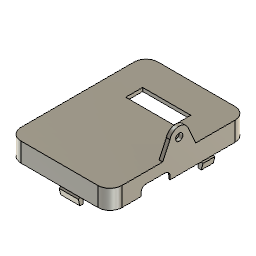
Wireless Motion Sensor (Autodesk Fusion 360 design; units mm, degrees)
Autodesk Fusion 360 part; units mm, degrees
sketch "perf board sketch" plane through (0, 0, 0) normal (0, 0, 1) x (1, 0, 0) in component "Perf"
  line L0 (16, 25) -> (-16, 25)
  line L1 (-16, 25) -> (-16, -25)
  line L2 (-16, -25) -> (16, -25)
  line L3 (16, -25) -> (16, 25)
  line L4 (16, 25) -> (-16, -25) construction
  line L5 (-16, 25) -> (16, -25) construction
  dimension "d12" = 32
  dimension "d13" = 50
  constraint horizontal L0
  constraint perpendicular L0 L1
  constraint parallel L0 L2
  constraint parallel L1 L3
  constraint coincident L4 origin
  constraint coincident L5 origin
  measures "d12" distance of L1.end L2.end
  measures "d13" distance of L0.end L1.end
extrude "Extrusion of the perf board body." add sketch "perf board sketch" along normal blind 1.2 makes body 1 in component "Perf"
sketch "dSensor board sketch" plane through (0, 0, 0) normal (0, 0, 1) x (1, 0, 0) in component "DSensor"
  line L0 (7, 3.1) -> (-13, 3.1)
  line L1 (-15.5, 5.6) -> (-15.5, 18.4)
  line L2 (-13, 20.9) -> (7, 20.9)
  line L3 (9.5, 18.4) -> (9.5, 5.6)
  line L4 (9.5, 3.1) -> (-15.5, 20.9) construction
  line L5 (-15.5, 3.1) -> (9.5, 20.9) construction
  line L6 (0, 2.5) -> (0, 20) construction
  line L7 (20, 0) -> (2.5, 0) construction
  line L8 (-3, 12) -> (-3, 17) construction
  line L9 (-3, 12) -> (-7, 12) construction
  circle A0 centre (-13.46, 18.86) radius 1.2
  circle A1 centre (7.46, 18.86) radius 1.2
  circle A2 centre (7.46, 5.14) radius 1.2
  circle A3 centre (-13.46, 5.14) radius 1.2
  arc A4 (-13, 20.9) -> (-15.5, 18.4) centre (-13, 18.4) ccw
  arc A5 (9.5, 18.4) -> (7, 20.9) centre (7, 18.4) ccw
  arc A6 (7, 3.1) -> (9.5, 5.6) centre (7, 5.6) ccw
  arc A7 (-15.5, 5.6) -> (-13, 3.1) centre (-13, 5.6) ccw
  point P0 (-3, 12)
  dimension "d16" = 25
  dimension "d17" = 17.8
  dimension "d18" = 3
  dimension "d19" = 12
  dimension "d20" = 2.4
  dimension "d21" = 2.04
  dimension "d22" = 2.04
  dimension "d23" = 2.5
  constraint horizontal L0
  constraint perpendicular L0 L1
  constraint parallel L0 L2
  constraint parallel L1 L3
  constraint coincident L4 P0
  constraint coincident L5 P0
  constraint coincident P0 L8.start
  constraint vertical L8
  constraint perpendicular L8 L9
  constraint symmetric L8 A0 A1
  constraint symmetric L9 A0 A3
  constraint symmetric L9 A1 A2
  constraint coincident L4.end L1
  constraint coincident L4.end L2
  constraint tangent L1 A4
  constraint tangent L2 A4
  constraint coincident L5.end L2
  constraint coincident L5.end L3
  constraint tangent L2 A5
  constraint tangent L3 A5
  constraint equal A4 A5
  constraint coincident L4.start L3
  constraint coincident L4.start L0
  constraint tangent L3 A6
  constraint tangent L0 A6
  constraint equal A4 A6
  constraint coincident L5.start L0
  constraint coincident L5.start L1
  constraint tangent L0 A7
  constraint tangent L1 A7
  constraint equal A4 A7
  measures "d16" distance of L4.end L5.end
  measures "d17" distance of L5.start L4.end
  measures "d18" distance of P0 L6
  measures "d19" distance of P0 L7
  measures "d20" diameter of A0
  measures "d21" distance of L1 A0.centre
  measures "d22" distance of L2 A0.centre
  measures "d23" radius of A4
extrude "Extrusion of the dSensor board body." add sketch "dSensor board sketch" along normal blind 1.6 separate body makes body 2 in component "DSensor"
sketch "wemos board sketch" plane through (0, 0, 0) normal (0, 0, 1) x (1, 0, 0) in component "Wemos"
  line L0 (17.5, 2) -> (-14.5, 2)
  line L1 (-17.5, -1) -> (-17.5, -20)
  line L2 (-14.5, -23) -> (17.5, -23)
  line L3 (17.5, -23) -> (17.5, 2)
  line L4 (17.5, 2) -> (-17.5, -23) construction
  line L5 (-17.5, 2) -> (17.5, -23) construction
  line L6 (-17.5, -1) -> (-14.5, 2)
  line L7 (-17.5, -20) -> (-14.5, -23)
  line L8 (17.5, -18) -> (16, -18)
  line L9 (16, -18) -> (16, -9.5)
  line L10 (16, -9.5) -> (17.5, -9.5)
  line L11 (17.5, -9.5) -> (17.5, -18)
  line L12 (0, 1.75) -> (0, 22.5)
  line L13 (20, 0) -> (2.5, 0)
  point P0 (0, -10.5)
  dimension "d26" = 35
  dimension "d27" = 25
  dimension "d28" = 3
  dimension "d29" = 3
  dimension "d30" = 3
  dimension "d31" = 3
  dimension "d32" = 5
  dimension "d33" = 8.5
  dimension "d34" = 10.5
  constraint horizontal L0
  constraint perpendicular L0 L1
  constraint parallel L0 L2
  constraint parallel L1 L3
  constraint coincident L4 P0
  constraint coincident L5 P0
  constraint coincident L5.start L1
  constraint coincident L5.start L0
  constraint coincident L4.end L1
  constraint coincident L4.end L2
  constraint horizontal L8
  constraint vertical L9
  constraint horizontal L10
  constraint vertical L11
  constraint coincident L3 L8.start
  constraint coincident P0 L12
  measures "d26" distance of L4.end L2.end
  measures "d27" distance of L5.start L4.end
  measures "d28" distance of L5.start L1.start
  measures "d29" distance of L5.start L0.end
  measures "d30" distance of L4.end L1.end
  measures "d31" distance of L4.end L2.start
  measures "d32" distance of L2 L8
  measures "d33" distance of L8 L10
  measures "d34" distance of P0 L13
extrude "Extrusion of the wemos board body." add sketch "wemos board sketch" along normal blind 1.2 separate body contours L0 L1 L2 L3 L6 L7 L8 L9 L10 makes body 3 in component "Wemos"
sketch "housing outline sketch" plane through (0, 0, 0) normal (0, 0, 1) x (1, 0, 0) in component "Housing"
  line L0 (-16, -28.5) -> (16, -28.5)
  line L1 (21, -23.5) -> (21, 23.5)
  line L2 (16, 28.5) -> (-16, 28.5)
  line L3 (-21, 23.5) -> (-21, -23.5)
  line L4 (-21, -28.5) -> (21, 28.5) construction
  line L5 (21, -28.5) -> (-21, 28.5) construction
  circle A0 centre (0, 34) radius 1.5
  circle A1 centre (0, 34) radius 2.5
  circle A2 centre (0, 34) radius 4
  line L6 (0, 1.75) -> (0, 22.5)
  line L7 (-3.8706, 35.0092) -> (-6.9059, 28.5)
  line L8 (-3.8706, 35.0092) -> (3.3115, 35.0092) construction
  line L9 (3.8706, 35.0092) -> (6.2397, 28.5)
  line L10 (20, 0) -> (2.5, 0)
  circle A3 centre (0, -34) radius 1.5
  circle A4 centre (0, -34) radius 2.5
  circle A5 centre (0, -34) radius 4
  line L11 (-3.8706, -35.0092) -> (-6.9059, -28.5)
  line L12 (3.8706, -35.0092) -> (6.2397, -28.5)
  arc A6 (-16, 28.5) -> (-21, 23.5) centre (-16, 23.5) ccw
  arc A7 (21, 23.5) -> (16, 28.5) centre (16, 23.5) ccw
  arc A8 (-21, -23.5) -> (-16, -28.5) centre (-16, -23.5) ccw
  arc A9 (16, -28.5) -> (21, -23.5) centre (16, -23.5) ccw
  line L13 (-19.5, 23.5) -> (-19.5, -23.5)
  arc A10 (-19.5, -23.5) -> (-16, -27) centre (-16, -23.5) ccw
  line L14 (-16, -27) -> (16, -27)
  arc A11 (16, -27) -> (19.5, -23.5) centre (16, -23.5) ccw
  line L15 (19.5, -23.5) -> (19.5, 23.5)
  arc A12 (19.5, 23.5) -> (16, 27) centre (16, 23.5) ccw
  line L16 (16, 27) -> (-16, 27)
  arc A13 (-16, 27) -> (-19.5, 23.5) centre (-16, 23.5) ccw
  line L17 (-20.1, 23.5) -> (-20.1, -23.5)
  arc A14 (-20.1, -23.5) -> (-16, -27.6) centre (-16, -23.5) ccw
  line L18 (-16, -27.6) -> (16, -27.6)
  arc A15 (16, -27.6) -> (20.1, -23.5) centre (16, -23.5) ccw
  line L19 (20.1, -23.5) -> (20.1, 23.5)
  arc A16 (20.1, 23.5) -> (16, 27.6) centre (16, 23.5) ccw
  line L20 (16, 27.6) -> (-16, 27.6)
  arc A17 (-16, 27.6) -> (-20.1, 23.5) centre (-16, 23.5) ccw
  line L21 (-20.4, 23.5) -> (-20.4, -23.5)
  arc A18 (-20.4, -23.5) -> (-16, -27.9) centre (-16, -23.5) ccw
  line L22 (-16, -27.9) -> (16, -27.9)
  arc A19 (16, -27.9) -> (20.4, -23.5) centre (16, -23.5) ccw
  line L23 (20.4, -23.5) -> (20.4, 23.5)
  arc A20 (20.4, 23.5) -> (16, 27.9) centre (16, 23.5) ccw
  line L24 (16, 27.9) -> (-16, 27.9)
  arc A21 (-16, 27.9) -> (-20.4, 23.5) centre (-16, 23.5) ccw
  line L25 (10, 9.1) -> (-10, 9.1)
  line L26 (-10, 9.1) -> (-10, 16.1)
  line L27 (-10, 16.1) -> (10, 16.1)
  line L28 (10, 16.1) -> (10, 9.1)
  line L29 (10, 9.1) -> (-10, 16.1) construction
  line L30 (-10, 9.1) -> (10, 16.1) construction
  line L31 (5, -15) -> (-10, -15)
  line L32 (-10, -15) -> (-10, -5)
  line L33 (-10, -5) -> (5, -5)
  line L34 (5, -5) -> (5, -15)
  line L35 (5, -15) -> (-10, -5) construction
  line L36 (-10, -15) -> (5, -5) construction
  line L37 (16, 25) -> (-16, 25)
  line L38 (-16, -25) -> (16, -25)
  line L39 (-7, 25) -> (-7, 23) construction
  line L40 (-5, -25) -> (-5, -23) construction
  line L41 (-5, -23) -> (-19.5, -23)
  line L42 (-5, -23) -> (-5, -27)
  line L43 (-5, 27) -> (-5, 23)
  line L44 (-5, 23) -> (-19.5, 23)
  line L45 (-10.5, 23) -> (-10.5, 27)
  line L46 (-10.5, -23) -> (-10.5, -27)
  line L47 (-14.5, -27) -> (-14.5, -23)
  line L48 (-14.5, 23) -> (-14.5, 27)
  line L49 (-3.8706, 35.0092) -> (-3.8706, 28.5) construction
  line L50 (-3.8706, 28.5) -> (-6.9059, 28.5) construction
  line L51 (-16, -27) -> (-16, -23)
  line L52 (-16, 23) -> (-16, 27)
  point P0 (0, 12.6)
  point P1 (-2.5, -10)
  dimension "d43" = 42
  dimension "d44" = 57
  dimension "d47" = 3
  dimension "d48" = 1
  dimension "d49" = 1.5
  dimension "d50" = 5.5
  dimension "d53" = 115
  dimension "d54" = 135
  dimension "d55" = 5
  dimension "d58" = -0.9
  dimension "d59" = -0.6
  dimension "d60" = 20
  dimension "d61" = 7
  dimension "d62" = 15
  dimension "d63" = 15
  dimension "d64" = 10
  dimension "d65" = 17
  dimension "d66" = 17
  dimension "d67" = 2
  dimension "d68" = 2
  dimension "d69" = 14.5
  dimension "d70" = 4
  dimension "d115" = 9
  dimension "d116" = 9
  dimension "d117" = 5
  dimension "d118" = 5
  constraint horizontal L0
  constraint perpendicular L0 L1
  constraint parallel L0 L2
  constraint parallel L1 L3
  constraint coincident L4 origin
  constraint coincident L5 origin
  constraint coincident A0.centre L6
  constraint horizontal L8
  constraint coincident A2 L7.start
  constraint coincident L2 L7.end
  constraint coincident A2 L9.start
  constraint coincident L2 L9.end
  constraint symmetric A0 L10 A3
  constraint symmetric A1 L10 A4
  constraint symmetric A2 L10 A5
  constraint symmetric L7.start L10 L11.start
  constraint symmetric L7.end L10 L11.end
  constraint symmetric L9.start L10 L12.start
  constraint symmetric L9.end L10 L12.end
  constraint coincident L5.end L3
  constraint coincident L5.end L2
  constraint tangent L3 A6
  constraint tangent L2 A6
  constraint coincident L4.end L2
  constraint coincident L4.end L1
  constraint tangent L2 A7
  constraint tangent L1 A7
  constraint equal A6 A7
  constraint coincident L4.start L3
  constraint coincident L4.start L0
  constraint tangent L3 A8
  constraint tangent L0 A8
  constraint equal A6 A8
  constraint coincident L5.start L1
  constraint coincident L5.start L0
  constraint tangent L1 A9
  constraint tangent L0 A9
  constraint equal A6 A9
  constraint horizontal L25
  constraint perpendicular L25 L26
  constraint parallel L25 L27
  constraint parallel L26 L28
  constraint coincident L29 P0
  constraint coincident L30 P0
  constraint coincident L6 P0
  constraint horizontal L31
  constraint perpendicular L31 L32
  constraint parallel L31 L33
  constraint parallel L32 L34
  constraint coincident L35 P1
  constraint coincident L36 P1
  constraint coincident L37 L39.start
  constraint perpendicular L37 L39
  constraint coincident L38 L40.start
  constraint perpendicular L38 L40
  constraint coincident L13 L41.end
  constraint perpendicular L13 L41
  constraint coincident L14 L42.end
  constraint perpendicular L14 L42
  constraint coincident L16 L43.start
  constraint perpendicular L37 L43
  constraint coincident L13 L44.end
  constraint perpendicular L13 L44
  constraint coincident L44 L45.start
  constraint coincident L16 L45.end
  constraint perpendicular L16 L45
  constraint coincident L41 L46.start
  constraint coincident L14 L46.end
  constraint perpendicular L14 L46
  constraint coincident L14 L47.start
  constraint coincident L41 L47.end
  constraint perpendicular L41 L47
  constraint coincident L44 L48.start
  constraint coincident L16 L48.end
  constraint perpendicular L16 L48
  constraint coincident L2 L49.end
  constraint perpendicular L2 L49
  constraint coincident L41 L51.end
  constraint perpendicular L41 L51
  constraint coincident L44 L52.start
  measures "d43" distance of L4.end L5.end
  measures "d44" distance of L5.start L4.end
  measures "d47" diameter of A0
  measures "d50" distance of L2 A0.centre
  measures "d53" angle of L7 L8
  measures "d54" angle of L7 L9
  measures "d55" radius of A6
  measures "d60" distance of L26.end L27.end
  measures "d61" distance of L25.end L26.end
  measures "d62" distance of L20 P0
  measures "d63" distance of L32.end L33.end
  measures "d64" distance of L31.end L32.end
  measures "d65" distance of L13 P1
  measures "d66" distance of L14 P1
  measures "d67" distance of L39.start L39.end
  measures "d68" distance of L40.start L40.end
  measures "d69" distance of L43.end L44.end
  measures "d70" distance of L43.start L43.end
  measures "d115" distance of L13 L46
  measures "d116" distance of L13 L45
  measures "d117" distance of L13 L47
  measures "d118" distance of L13 L48
extrude "Extrusion of the housing's bottom base body." add sketch "housing outline sketch" along normal blind 1.5 from surface at -9.5 separate body contours L0 L1 L2 L3 A6 A7 A8 A9 | L0 A5 L11 L12 | A5 | L2 A2 L7 L9 | A2 | A1 | L6 L25 L26 L27 | L6 L25 L27 L28 | A4 | L13 A13 L44 L52 | L13 L14 A11 L15 A12 L16 L41 L42 L43 L44 | L16 L37 L48 L52 | L13 A10 L41 L51 | L37 L44 L48 L52 | L16 L37 L45 L48 | L38 L41 L47 L51 | L37 L44 L45 L48 | L16 L37 L43 L45 | L14 L38 L47 L51 | L38 L41 L46 L47 | L37 L43 L44 L45 | L14 L38 L46 L47 | L38 L41 L42 L46 | L14 L38 L42 L46 | L17 A14 L18 A15 L19 A16 L20 A17 | L21 A18 L22 A19 L23 A20 L24 A21 | L31 L32 L33 L34 makes body 4 in component "Housing"
extrude "Extrusion of the housing's bottom pcb stand off." add sketch "housing outline sketch" along normal blind 3 from surface at -8 contours L31 L32 L33 L34 bodies 4 in component "Housing"
extrude "Extrusion of the housing's bottom body outside walls." add sketch "housing outline sketch" against normal up to surface (8 mm away) contours L0 L1 L2 L3 A6 A7 A8 A9 | L17 A14 L18 A15 L19 A16 L20 A17 | L21 A18 L22 A19 L23 A20 L24 A21 bodies 4 in component "Housing"
extrude "Extrusion of the housing's bottom mounting holes support." add sketch "housing outline sketch" along normal blind 1.5 from surface at -8 contours L0 A5 L11 L12 | A5 | L2 A2 L7 L9 | A2 bodies 4 in component "Housing"
extrude "Extrusion of the housing's bottom body walls rim." add sketch "housing outline sketch" along normal blind 2.5 contours L17 A14 L18 A15 L19 A16 L20 A17 bodies 4 in component "Housing"
extrude "Extrusion of the housing's top body base." add sketch "housing outline sketch" along normal blind 1.5 from surface at 6.5 separate body contours L0 L1 L2 L3 A6 A7 A8 A9 | L13 A13 L44 L52 | L13 L14 A11 L15 A12 L16 L41 L42 L43 L44 | L16 L37 L48 L52 | L13 A10 L41 L51 | L37 L44 L48 L52 | L16 L37 L45 L48 | L38 L41 L47 L51 | L37 L44 L45 L48 | L16 L37 L43 L45 | L14 L38 L47 L51 | L38 L41 L46 L47 | L37 L43 L44 L45 | L14 L38 L46 L47 | L38 L41 L42 L46 | L14 L38 L42 L46 | L17 A14 L18 A15 L19 A16 L20 A17 | L21 A18 L22 A19 L23 A20 L24 A21 | L31 L32 L33 L34 makes body 5 in component "Housing"
extrude "Extrusion of the housing's top body outside walls." add sketch "housing outline sketch" along normal up to surface (6.5 mm away) contours L0 L1 L2 L3 A6 A7 A8 A9 | L17 A14 L18 A15 L19 A16 L20 A17 | L21 A18 L22 A19 L23 A20 L24 A21 bodies 5 in component "Housing"
extrude "Extrusion cutout of the housing's top body walls rim." cut sketch "housing outline sketch" along normal blind 2.8 contours L17 A14 L18 A15 L19 A16 L20 A17 | L21 A18 L22 A19 L23 A20 L24 A21 bodies 5 in component "Housing"
sketch "components outline sketch" plane through (0, 0, 1.6) normal (0, 0, 1) x (1, 0, 0) in component "DSensor"
  circle A0 centre (-13.46, 5.14) radius 1.2
  circle A1 centre (-13.46, 18.86) radius 1.2
  circle A2 centre (7.46, 18.86) radius 1.2
  circle A3 centre (7.46, 5.14) radius 1.2
  arc A4 (-13, 20.9) -> (-15.5, 18.4) centre (-13, 18.4) ccw
  line L0 (-15.5, 18.4) -> (-15.5, 5.6)
  arc A5 (-15.5, 5.6) -> (-13, 3.1) centre (-13, 5.6) ccw
  line L1 (-13, 3.1) -> (7, 3.1)
  arc A6 (7, 3.1) -> (9.5, 5.6) centre (7, 5.6) ccw
  line L2 (9.5, 5.6) -> (9.5, 18.4)
  arc A7 (9.5, 18.4) -> (7, 20.9) centre (7, 18.4) ccw
  line L3 (7, 20.9) -> (-13, 20.9)
  line L4 (-1.5, 9.5) -> (-4.5, 9.5)
  line L5 (-4.5, 9.5) -> (-4.5, 14.5)
  line L6 (-4.5, 14.5) -> (-1.5, 14.5)
  line L7 (-1.5, 14.5) -> (-1.5, 9.5)
  line L8 (-1.5, 9.5) -> (-4.5, 14.5) construction
  line L9 (-4.5, 9.5) -> (-1.5, 14.5) construction
  line L10 (-11, 8.75) -> (-15.5, 8.75)
  line L11 (-15.5, 8.75) -> (-15.5, 15.25)
  line L12 (-15.5, 15.25) -> (-11, 15.25)
  line L13 (-11, 15.25) -> (-11, 8.75)
  line L14 (-11, 8.75) -> (-15.5, 15.25) construction
  line L15 (-15.5, 8.75) -> (-11, 15.25) construction
  line L16 (9.5, 8.75) -> (5, 8.75)
  line L17 (5, 8.75) -> (5, 15.25)
  line L18 (5, 15.25) -> (9.5, 15.25)
  line L19 (9.5, 15.25) -> (9.5, 8.75)
  line L20 (9.5, 8.75) -> (5, 15.25) construction
  line L21 (5, 8.75) -> (9.5, 15.25) construction
  circle A8 centre (-13.46, 5.14) radius 1.2
  circle A9 centre (-13.46, 18.86) radius 1.2
  circle A10 centre (7.46, 18.86) radius 1.2
  circle A11 centre (7.46, 5.14) radius 1.2
  arc A12 (-13, 20.9) -> (-15.5, 18.4) centre (-13, 18.4) ccw
  line L22 (-15.5, 18.4) -> (-15.5, 5.6)
  arc A13 (-15.5, 5.6) -> (-13, 3.1) centre (-13, 5.6) ccw
  line L23 (-13, 3.1) -> (7, 3.1)
  arc A14 (7, 3.1) -> (9.5, 5.6) centre (7, 5.6) ccw
  line L24 (9.5, 5.6) -> (9.5, 18.4)
  arc A15 (9.5, 18.4) -> (7, 20.9) centre (7, 18.4) ccw
  line L25 (7, 20.9) -> (-13, 20.9)
  point P0 (-3, 12)
  point P1 (-13.25, 12)
  point P2 (7.25, 12)
  dimension "d85" = 3
  dimension "d86" = 5
  dimension "d87" = 12.5
  dimension "d88" = 8.9
  dimension "d89" = 4.5
  dimension "d90" = 6.5
  dimension "d91" = 8.9
  dimension "d92" = 6.5
  dimension "d93" = 4.5
  dimension "d94" = 8.9
  constraint horizontal L4
  constraint perpendicular L4 L5
  constraint parallel L4 L6
  constraint parallel L5 L7
  constraint coincident L8 P0
  constraint coincident L9 P0
  constraint horizontal L10
  constraint perpendicular L10 L11
  constraint parallel L10 L12
  constraint parallel L11 L13
  constraint coincident L14 P1
  constraint coincident L15 P1
  constraint collinear L0 L11
  constraint horizontal L16
  constraint perpendicular L16 L17
  constraint parallel L16 L18
  constraint parallel L17 L19
  constraint coincident L20 P2
  constraint coincident L21 P2
  constraint collinear L2 L19
  measures "d85" distance of L5.end L6.end
  measures "d86" distance of L4.end L5.end
  measures "d87" distance of L0 P0
  measures "d88" distance of L3 P0
  measures "d89" distance of L11.end L12.end
  measures "d90" distance of L10.end L11.end
  measures "d91" distance of L1 P1
  measures "d92" distance of L16 L18
  measures "d93" distance of L17 L19
  measures "d94" distance of L1 P2
extrude "Extrusion of the dSensor's sensor body." add sketch "components outline sketch" along normal blind 1.5 separate body contours L4 L5 L6 L7 makes body 6 in component "DSensor"
extrude "Extrusion of the dSensor's connectors bodies." add sketch "components outline sketch" along normal blind 3 separate body contours L0 L10 L11 L12 L13 L22 | L2 L16 L17 L18 L19 L24 makes body 7 at (-14, 13.0833, 1.6) makes body 8 at (6.5, 13.0833, 1.6) in component "DSensor"
sketch "components outline sketch (2)" plane through (0, 0, 1.2) normal (0, 0, 1) x (-1, 0, 0) in component "Wemos"
  line L0 (17.5, 1) -> (17.5, 20)
  line L1 (17.5, 20) -> (14.5, 23)
  line L2 (14.5, 23) -> (-17.5, 23)
  line L3 (-17.5, 23) -> (-17.5, 18)
  line L4 (-17.5, 18) -> (-16, 18)
  line L5 (-16, 18) -> (-16, 9.5)
  line L6 (-16, 9.5) -> (-17.5, 9.5)
  line L7 (-17.5, 9.5) -> (-17.5, -2)
  line L8 (-17.5, -2) -> (14.5, -2)
  line L9 (14.5, -2) -> (17.5, 1)
  line L10 (-4.5, 16.5) -> (10.5, 16.5)
  line L11 (10.5, 16.5) -> (10.5, 4.5)
  line L12 (10.5, 4.5) -> (-4.5, 4.5)
  line L13 (-4.5, 4.5) -> (-4.5, 16.5)
  line L14 (-4.5, 16.5) -> (10.5, 4.5) construction
  line L15 (10.5, 16.5) -> (-4.5, 4.5) construction
  point P0 (3, 10.5)
  dimension "d99" = 15
  dimension "d100" = 12
  dimension "d101" = 12.5
  dimension "d102" = 7
  constraint horizontal L10
  constraint perpendicular L10 L11
  constraint parallel L10 L12
  constraint parallel L11 L13
  constraint coincident L14 P0
  constraint coincident L15 P0
  measures "d99" distance of L11.end L12.end
  measures "d100" distance of L10.end L11.end
  measures "d101" distance of L2 P0
  measures "d102" distance of L0 L11
extrude "Extrusion of the wemos's wifi mod body." add sketch "components outline sketch (2)" along normal blind 3 separate body contours L10 L11 L12 L13 makes body 9 in component "Wemos"
sketch "headers outline sketch" plane through (0, 0, 0) normal (0, 0, -1) x (1, 0, 0) in component "Headers"
  line L0 (16, -25) -> (16, 25)
  line L1 (16, 25) -> (-16, 25)
  line L2 (-16, 25) -> (-16, -25)
  line L3 (-16, -25) -> (16, -25)
  line L4 (-12.7415, 20.1248) -> (12, 20.1248)
  line L5 (12, 20.1248) -> (12, 17.6248)
  line L6 (12, 17.6248) -> (-12.7415, 17.6248)
  line L7 (-12.7415, 17.6248) -> (-12.7415, 20.1248)
  line L8 (-12.7415, 3.2784) -> (12, 3.2784)
  line L9 (12, 3.2784) -> (12, 0.7784)
  line L10 (12, 0.7784) -> (-12.7415, 0.7784)
  line L11 (-12.7415, 0.7784) -> (-12.7415, 3.2784)
  line L12 (-11, -17) -> (5.4615, -17)
  line L13 (5.4615, -17) -> (5.4615, -19.5)
  line L14 (5.4615, -19.5) -> (-11, -19.5)
  line L15 (-11, -19.5) -> (-11, -17)
  dimension "d105" = 2.5
  dimension "d106" = 2.5
  dimension "d107" = 2.5
  constraint horizontal L4
  constraint vertical L5
  constraint horizontal L6
  constraint vertical L7
  constraint horizontal L8
  constraint vertical L9
  constraint horizontal L10
  constraint vertical L11
  constraint horizontal L12
  constraint vertical L13
  constraint horizontal L14
  constraint vertical L15
  measures "d105" distance of L4.start L6.end
  measures "d106" distance of L8.start L10.end
  measures "d107" distance of L12.start L14.end
extrude "Extrusion of the header's rows bodies." add sketch "headers outline sketch" along normal blind 5 separate body contours L4 L5 L6 L7 | L8 L9 L10 L11 | L12 L13 L14 L15 makes body 10 at (-4.4943, -20.1248, -1.6667) makes body 11 at (-4.4943, -3.2784, -1.6667) makes body 12 at (-5.5128, 17, -1.6667) in component "Headers"
extrude "Extrusion of the housing's bottom body pcb's top supports." add sketch "housing outline sketch" against normal blind 1.5 contours L13 A13 L44 L52 | L16 L37 L48 L52 | L13 A10 L41 L51 | L37 L44 L48 L52 | L16 L37 L45 L48 | L38 L41 L47 L51 | L37 L44 L45 L48 | L14 L38 L47 L51 | L38 L41 L46 L47 | L14 L38 L46 L47 bodies 4 in component "Housing"
extrude "Extrusion of the housing's bottom pcb's bottom supports." add sketch "housing outline sketch" against normal blind 1.5 from surface at -3 contours L13 A13 L44 L52 | L16 L37 L48 L52 | L13 A10 L41 L51 | L37 L44 L48 L52 | L16 L37 L45 L48 | L38 L41 L47 L51 | L37 L44 L45 L48 | L16 L37 L43 L45 | L14 L38 L47 L51 | L38 L41 L46 L47 | L37 L43 L44 L45 | L14 L38 L46 L47 | L38 L41 L42 L46 | L14 L38 L42 L46 bodies 4 in component "Housing"
extrude "Extrusion of the housing's bottom pcb's supports stop." add sketch "housing outline sketch" against normal up to surface (3 mm away) contours L13 A13 L44 L52 | L13 A10 L41 L51 bodies 4 in component "Housing"
sketch "housing's snap insert outline sketch x-z plane" plane through (0, -27, 0) normal (0, 1, 0) x (-1, 0, 0) in component "Housing"
  line L0 (16, -1.5) -> (10.5, -1.5)
  line L1 (10.5, -1.5) -> (10.5, 0)
  line L2 (10.5, 0) -> (16, 0)
  line L3 (16, 0) -> (16, 2.5)
  line L4 (16, 2.5) -> (-16, 2.5)
  line L5 (-16, 2.5) -> (-16, -8)
  line L6 (-16, -8) -> (16, -8)
  line L7 (16, -8) -> (16, -4.5)
  line L8 (16, -4.5) -> (5, -4.5)
  line L9 (5, -4.5) -> (5, -3)
  line L10 (5, -3) -> (16, -3)
  line L11 (1.15, -1.1) -> (-7.15, -1.1)
  line L12 (-7.15, -1.1) -> (-7.15, -4.9)
  line L13 (-7.15, -4.9) -> (1.15, -4.9)
  line L14 (1.15, -4.9) -> (1.15, -1.1)
  line L15 (1.15, -1.1) -> (-7.15, -4.9) construction
  line L16 (-7.15, -1.1) -> (1.15, -4.9) construction
  line L17 (1, 7.4) -> (-7, 7.4)
  line L18 (-7, 7.4) -> (-7, -4.6)
  line L19 (-7, -4.6) -> (1, -4.6)
  line L20 (1, -4.6) -> (1, 7.4)
  line L21 (1, 7.4) -> (-7, -4.6) construction
  line L22 (-7, 7.4) -> (1, -4.6) construction
  line L23 (16, -3) -> (16, -1.5)
  line L24 (-7.15, -1.1) -> (-7.15, -3.1) construction
  line L25 (-7.15, -3.1) -> (1.15, -3.1)
  point P0 (-3, -3)
  point P1 (-3, 1.4)
  dimension "d127" = 8.3
  dimension "d128" = 3.8
  dimension "d129" = 5
  dimension "d130" = 13
  dimension "d157" = 8
  dimension "d158" = 12
  dimension "d159" = 13
  dimension "d160" = 0.3
  dimension "d205" = 2
  constraint horizontal L11
  constraint perpendicular L11 L12
  constraint parallel L11 L13
  constraint parallel L12 L14
  constraint coincident L15 P0
  constraint coincident L16 P0
  constraint horizontal L17
  constraint perpendicular L17 L18
  constraint parallel L17 L19
  constraint parallel L18 L20
  constraint coincident L21 P1
  constraint coincident L22 P1
  constraint perpendicular L11 L24
  constraint coincident L14 L25.end
  constraint perpendicular L14 L25
  measures "d127" distance of L12.end L13.end
  measures "d128" distance of L11.end L12.end
  measures "d129" distance of L6 P0
  measures "d130" distance of L5 P0
  measures "d157" distance of L18.end L19.end
  measures "d158" distance of L17.end L18.end
  measures "d159" distance of L5 P1
  measures "d160" distance of L13 L19
  measures "d205" distance of L11.end L24.end
sketch "housing's snap insert outline sketch z-y plane" plane through (-19.5, 0, 0) normal (1, 0, 0) x (0, 1, 0) in component "Housing"
  line L0 (23, -4.5) -> (23, 0)
  line L1 (23, 0) -> (23.5, 0)
  line L2 (23.5, 0) -> (23.5, 2.5)
  line L3 (23.5, 2.5) -> (-23.5, 2.5)
  line L4 (-23.5, 2.5) -> (-23.5, 0)
  line L5 (-23.5, 0) -> (-23, 0)
  line L6 (-23, 0) -> (-23, -4.5)
  line L7 (-23, -4.5) -> (-23.5, -4.5)
  line L8 (-23.5, -4.5) -> (-23.5, -8)
  line L9 (-23.5, -8) -> (23.5, -8)
  line L10 (23.5, -8) -> (23.5, -4.5)
  line L11 (23.5, -4.5) -> (23, -4.5)
  line L12 (-10.85, -4.75) -> (-16.15, -4.75)
  line L13 (-16.15, -4.75) -> (-16.15, -1.25)
  line L14 (-16.15, -1.25) -> (-10.85, -1.25)
  line L15 (-10.85, -1.25) -> (-10.85, -4.75)
  line L16 (-10.85, -4.75) -> (-16.15, -1.25) construction
  line L17 (-16.15, -4.75) -> (-10.85, -1.25) construction
  line L18 (0, 2.5) -> (0, 20)
  line L19 (16.15, -1.25) -> (10.85, -1.25)
  line L20 (16.15, -4.75) -> (16.15, -1.25)
  line L21 (10.85, -4.75) -> (16.15, -4.75)
  line L22 (10.85, -1.25) -> (10.85, -4.75)
  line L23 (-11, 7.55) -> (-16, 7.55)
  line L24 (-16, 7.55) -> (-16, -4.45)
  line L25 (-16, -4.45) -> (-11, -4.45)
  line L26 (-11, -4.45) -> (-11, 7.55)
  line L27 (-11, 7.55) -> (-16, -4.45) construction
  line L28 (-16, 7.55) -> (-11, -4.45) construction
  point P0 (-13.5, -3)
  point P1 (-13.5, 1.55)
  dimension "d133" = 5.3
  dimension "d134" = 3.5
  dimension "d135" = 10
  dimension "d136" = 5
  dimension "d161" = 5
  dimension "d162" = 12
  dimension "d163" = 10
  dimension "d164" = 0.3
  constraint horizontal L12
  constraint perpendicular L12 L13
  constraint parallel L12 L14
  constraint parallel L13 L15
  constraint coincident L16 P0
  constraint coincident L17 P0
  constraint symmetric L12.start L18 L21.start
  constraint symmetric L12.end L18 L20.start
  constraint symmetric L13.end L18 L19.start
  constraint symmetric L14.end L18 L19.end
  constraint horizontal L23
  constraint perpendicular L23 L24
  constraint parallel L23 L25
  constraint parallel L24 L26
  constraint coincident L27 P1
  constraint coincident L28 P1
  measures "d133" distance of L13.end L14.end
  measures "d134" distance of L12.end L13.end
  measures "d135" distance of L8 P0
  measures "d136" distance of L9 P0
  measures "d161" distance of L24.end L25.end
  measures "d162" distance of L23.end L24.end
  measures "d163" distance of L8 P1
  measures "d164" distance of L12 L25
sketch "housing's snap insert outline sketch z-x plane" plane through (0, 27, 0) normal (0, -1, 0) x (1, 0, 0) in component "Housing"
  line L0 (-16, -3) -> (-5, -3)
  line L1 (-5, -3) -> (-5, -4.5)
  line L2 (-5, -4.5) -> (-16, -4.5)
  line L3 (-16, -4.5) -> (-16, -8)
  line L4 (-16, -8) -> (16, -8)
  line L5 (16, -8) -> (16, 2.5)
  line L6 (16, 2.5) -> (-16, 2.5)
  line L7 (-16, 2.5) -> (-16, 0)
  line L8 (-16, 0) -> (-10.5, 0)
  line L9 (-10.5, 0) -> (-10.5, -1.5)
  line L10 (-10.5, -1.5) -> (-16, -1.5)
  line L11 (-1.15, -1.1) -> (7.15, -1.1)
  line L12 (-1.15, -4.9) -> (-1.15, -1.1)
  line L13 (7.15, -4.9) -> (-1.15, -4.9)
  line L14 (7.15, -1.1) -> (7.15, -4.9)
  line L15 (-16, -1.5) -> (-16, -3)
sketch "housing's y-z plane outline sketch." plane through (19.5, 0, 0) normal (-1, 0, 0) x (0, -1, 0) in component "Housing"
  line L0 (-23.5, -8) -> (23.5, -8)
  line L1 (23.5, -8) -> (23.5, 2.5)
  line L2 (23.5, 2.5) -> (-23.5, 2.5)
  line L3 (-23.5, 2.5) -> (-23.5, -8)
  line L4 (-10.85, -1.25) -> (-10.85, -4.75)
  line L5 (-16.15, -4.75) -> (-16.15, -1.25)
  line L6 (-16.15, -1.25) -> (-10.85, -1.25)
  line L7 (-10.85, -4.75) -> (-16.15, -4.75)
  line L8 (13.5, -2.5) -> (5.5, -2.5)
  line L9 (3.5, -0.5) -> (3.5, 1.5)
  line L10 (5.5, 3.5) -> (13.5, 3.5)
  line L11 (15.5, 1.5) -> (15.5, -0.5)
  line L12 (15.5, -2.5) -> (3.5, 3.5) construction
  line L13 (3.5, -2.5) -> (15.5, 3.5) construction
  arc A0 (5.5, 3.5) -> (3.5, 1.5) centre (5.5, 1.5) ccw
  arc A1 (15.5, 1.5) -> (13.5, 3.5) centre (13.5, 1.5) ccw
  arc A2 (3.5, -0.5) -> (5.5, -2.5) centre (5.5, -0.5) ccw
  arc A3 (13.5, -2.5) -> (15.5, -0.5) centre (13.5, -0.5) ccw
  point P0 (9.5, 0.5)
  dimension "d146" = 12
  dimension "d147" = 6
  dimension "d148" = 14
  dimension "d150" = 5
  dimension "d151" = 2
  constraint horizontal L8
  constraint perpendicular L8 L9
  constraint parallel L8 L10
  constraint parallel L9 L11
  constraint coincident L12 P0
  constraint coincident L13 P0
  constraint coincident L12.end L9
  constraint coincident L12.end L10
  constraint tangent L9 A0
  constraint tangent L10 A0
  constraint coincident L13.end L10
  constraint coincident L13.end L11
  constraint tangent L10 A1
  constraint tangent L11 A1
  constraint equal A0 A1
  constraint coincident L13.start L9
  constraint coincident L13.start L8
  constraint tangent L9 A2
  constraint tangent L8 A2
  constraint equal A0 A2
  constraint coincident L12.start L8
  constraint coincident L12.start L11
  constraint tangent L8 A3
  constraint tangent L11 A3
  constraint equal A0 A3
  measures "d146" distance of L12.end L13.end
  measures "d147" distance of L13.start L12.end
  measures "d148" distance of L1 P0
  measures "d150" distance of L2 L8
  measures "d151" radius of A0
extrude "Extrusion cutout of the housing's bottom snap inserts z-y plane." cut sketch "housing's snap insert outline sketch z-y plane" against normal blind 0.8 contours L14 L24 L25 L26 | L12 L13 L14 L15 L24 L25 L26 | L19 L20 L21 L22 bodies 4 in component "Housing"
extrude "Extrusion cutout of the housing's bottom snap insert x-z plane." cut sketch "housing's snap insert outline sketch x-z plane" against normal blind 0.8 contours L11 L18 L20 L25 | L11 L14 L20 L25 | L11 L12 L18 L25 | L12 L13 L14 L18 L19 L20 L25 | L18 L19 L20 L25 bodies 4 in component "Housing"
extrude "Extrusion cutout of the housing's bottom snap insert z-x plane." cut sketch "housing's snap insert outline sketch z-x plane" against normal blind 0.8 contours L11 L12 L13 L14 bodies 4 in component "Housing"
extrude "Extrusion cutout of the housing's bottom snap insert z-y plane." cut sketch "housing's y-z plane outline sketch." against normal blind 0.8 contours L4 L5 L6 L7 bodies 4 in component "Housing"
extrude "Extrusion cutout of the housing's usb hole." cut sketch "housing's y-z plane outline sketch." against normal blind 15 contours L2 L10 A0 A1 | L2 L8 L9 L11 A0 A1 A2 A3 bodies 4 5 in component "Housing"
extrude "Extrude26" cut sketch "housing's snap insert outline sketch x-z plane" along normal blind 59 and the other way blind 13 contours L11 L18 L20 L25 | L11 L14 L20 L25 | L11 L12 L18 L25 bodies 4 in component "Housing"
extrude "Extrusion of bSnap's body." add sketch "housing's snap insert outline sketch x-z plane" along normal blind 1.4 separate body contours L4 L11 L18 L20 | L4 L17 L18 L20 | L11 L18 L20 L25 | L18 L19 L20 L25 makes body 13 in component "Housing"
sketch "bSnap shaping sketch" plane through (7, 0, 0) normal (1, 0, 0) x (0, 1, 0) in component "Housing"
  line L0 (-27, 7.4) -> (-27, -4.6)
  line L1 (-27, -4.6) -> (-25.6, -4.6)
  line L2 (-25.6, -4.6) -> (-25.6, 7.4)
  line L3 (-25.6, 7.4) -> (-27, 7.4)
  line L4 (-27, -4.6) -> (-27.6403, -1.9654)
  line L5 (-27, -4.6) -> (-26.6, -4.6) construction
  line L6 (-26.6, -4.6) -> (-26.6, -0.2748) construction
  line L7 (-26.6, -0.2748) -> (-27, -0.2748) construction
  line L8 (-27.6403, -1.9654) -> (-26.6, -1.065)
  line L9 (-26.6, -1.065) -> (-26.6, 3.6894)
  line L10 (-26.6, 3.6894) -> (-27, 4.5)
  line L11 (-27.6403, -1.9654) -> (-26.6, -1.9654) construction
  line L12 (-26.6, 3.6894) -> (-27, 3.6894) construction
  line L13 (-27, 3.6894) -> (-27, 4.5) construction
  dimension "d167" = 0.4
  constraint coincident L0.end L1.start
  constraint perpendicular L0 L5
  constraint perpendicular L5 L6
  constraint coincident L0 L7.end
  constraint perpendicular L0 L7
  constraint coincident L6 L8.end
  constraint perpendicular L7 L9
  constraint coincident L0 L10.end
  constraint coincident L6 L11.end
  constraint perpendicular L6 L11
  constraint coincident L0 L12.end
  constraint perpendicular L0 L12
  measures "d167" distance of L0.end L5.end
extrude "Extrusion cutout of the bSnap body." cut sketch "bSnap shaping sketch" against normal blind 14 contours L0 L8 L9 L10 bodies 13 in component "Housing"
extrude "Extrusion of the bSnap lip." add sketch "bSnap shaping sketch" against normal blind 8 contours L0 L4 L8 bodies 13 in component "Housing"
mirror "Mirror of the bSnap." about plane through (0, 0, 0) normal (0, 1, 0) of bodies 13 makes body 14 in component "Housing"
extrude "Extrusion of the sSnap's body." add sketch "housing's snap insert outline sketch z-y plane" along normal blind 1.4 separate body contours L3 L14 L24 L26 | L3 L23 L24 L26 | L14 L24 L25 L26 makes body 15 in component "Housing"
sketch "sSnap shaping sketch" plane through (0, -16, 0) normal (0, -1, 0) x (1, 0, 0) in component "Housing"
  line L0 (-19.5, 7.55) -> (-19.5, -4.45)
  line L1 (-19.5, -4.45) -> (-18.1, -4.45)
  line L2 (-18.1, -4.45) -> (-18.1, 7.55)
  line L3 (-18.1, 7.55) -> (-19.5, 7.55)
  line L4 (-19.5, -4.45) -> (-19.1, -4.45) construction
  line L5 (-19.1, -4.45) -> (-19.1, 0) construction
  line L6 (-19.1, -4.45) -> (-19.1, -1.815) construction
  line L7 (-19.1, -1.8077) -> (-20.14, -1.8077) construction
  line L8 (-19.1, -1.815) -> (-19.1, -0.915) construction
  line L9 (-19.5, -4.45) -> (-20.14, -1.8077)
  line L10 (-20.14, -1.8077) -> (-19.1, -0.915)
  line L11 (-19.1, -0.915) -> (-19.1, 3.839)
  line L12 (-19.1, 3.839) -> (-19.5, 3.839) construction
  line L13 (-19.5, 3.839) -> (-19.5, 4.65) construction
  line L14 (-19.5, 4.65) -> (-19.1, 3.839)
  dimension "d178" = 2.635
  dimension "d179" = 1.04
  dimension "d180" = 0.9
  dimension "d181" = 4.754
  dimension "d182" = 0.811
  constraint coincident L0.end L1.start
  constraint coincident L1 L4.end
  constraint perpendicular L1 L5
  constraint perpendicular L4 L6
  constraint coincident L5 L7.start
  constraint perpendicular L0 L7
  constraint perpendicular L7 L8
  constraint parallel L8 L11
  constraint coincident L0 L12.end
  constraint perpendicular L0 L12
  constraint perpendicular L12 L13
  measures "d178" distance of L4.end L6.end
  measures "d179" distance of L7.start L7.end
  measures "d180" distance of L6.end L8.end
  measures "d181" distance of L8.end L11.end
  measures "d182" distance of L12.end L13.end
extrude "Extrusion cutout of sSnap's body." cut sketch "sSnap shaping sketch" against normal blind 9 contours L0 L10 L11 L14 bodies 15 in component "Housing"
extrude "Extrusion of the sSnap's lip." add sketch "sSnap shaping sketch" against normal blind 5 contours L0 L9 L10 bodies 15 in component "Housing"
mirror "Mirror of the sSnap same plane." about plane through (0, 0, 0) normal (0, 1, 0) of bodies 15 makes body 16 in component "Housing"
mirror "Mirror of the sSnap different plane." about plane through (0, 0, 0) normal (1, 0, 0) of bodies 16 makes body 17 in component "Housing"
combine "Combining of the snaps to the housing's top body." operation add target body 5 tool bodies 13 14 15 16 17 in component "Housing"
sketch "housing's side mounting hole sketch" plane through (21, 0, 0) normal (1, 0, 0) x (0, 1, 0) in component "Housing"
  arc A0 (-3.5, 1.5) -> (-5.5, 3.5) centre (-5.5, 1.5) ccw
  line L0 (-3.5, 0) -> (23.5, 0)
  line L1 (23.5, 0) -> (23.5, 8)
  line L2 (23.5, 8) -> (-23.5, 8)
  line L3 (-23.5, 8) -> (-23.5, 0)
  line L4 (-23.5, 0) -> (-15.5, 0)
  arc A1 (-13.5, 3.5) -> (-15.5, 1.5) centre (-13.5, 1.5) ccw
  line L5 (-13.5, 3.5) -> (-5.5, 3.5)
  line L6 (-3.5, 0) -> (-3.5, -0.5)
  arc A2 (-5.5, -2.5) -> (-3.5, -0.5) centre (-5.5, -0.5) ccw
  line L7 (-5.5, -2.5) -> (-13.5, -2.5)
  arc A3 (-15.5, -0.5) -> (-13.5, -2.5) centre (-13.5, -0.5) ccw
  line L8 (-15.5, -0.5) -> (-15.5, 0)
  line L9 (-15.5, 0) -> (-23.5, 0)
  line L10 (-23.5, 0) -> (-23.5, -9.5)
  line L11 (-23.5, -9.5) -> (23.5, -9.5)
  line L12 (23.5, -9.5) -> (23.5, 0)
  circle A4 centre (0.3056, 13.5) radius 1.5
  circle A5 centre (0.3056, 13.5) radius 2.5
  circle A6 centre (0.3056, 13.5) radius 4
  line L13 (4.1763, 8) -> (4.1763, 14.509) construction
  line L14 (4.1763, 8) -> (7.2113, 8) construction
  line L15 (4.1763, 14.509) -> (7.2113, 8)
  line L16 (0.3056, 13.5) -> (0.3056, 9) construction
  line L17 (-3.565, 14.509) -> (-6.6, 8)
  line L18 (12.3271, 8) -> (12.3271, -9.5) construction
  line L19 (12.3271, -0.75) -> (7.495, -0.75) construction
  line L20 (4.1763, -16.009) -> (7.2113, -9.5)
  circle A7 centre (0.3056, -15) radius 4
  circle A8 centre (0.3056, -15) radius 2.5
  circle A9 centre (0.3056, -15) radius 1.5
  line L21 (-3.565, -16.009) -> (-6.6, -9.5)
  line L22 (-15.5, 0) -> (-15.5, 1.5)
  line L23 (-3.5, 1.5) -> (-3.5, 0)
  line L24 (23.5, 0) -> (-3.5, 0)
  dimension "d191" = 3
  dimension "d192" = 1
  dimension "d193" = 1.5
  dimension "d194" = 5.5
  dimension "d195" = 6.509
  dimension "d196" = 3.035
  constraint coincident L2 L13.start
  constraint perpendicular L2 L13
  constraint coincident A6 L13.end
  constraint perpendicular L13 L14
  constraint coincident A4.centre A5.centre
  constraint vertical L16
  constraint symmetric L13.end L16 L17.start
  constraint symmetric L14.end L16 L17.end
  constraint coincident L2 L18.start
  constraint coincident L11 L18.end
  constraint perpendicular L11 L18
  constraint midpoint L18 L19.start
  constraint perpendicular L18 L19
  constraint symmetric A4 L19 A9
  constraint symmetric A5 L19 A8
  constraint symmetric A6 L19 A7
  constraint symmetric L13.end L19 L20.start
  constraint symmetric L14.end L19 L20.end
  constraint symmetric L17.start L19 L21.start
  constraint symmetric L17.end L19 L21.end
  measures "d191" diameter of A4
  measures "d194" distance of L2 A4.centre
  measures "d195" distance of L13.start L13.end
  measures "d196" distance of L13.start L14.end
extrude "Extrusion of the housing's side mounts base." add sketch "housing's side mounting hole sketch" against normal blind 1.5 contours L2 A6 L15 L17 | L11 L20 A7 L21 | A6 | A7 | A5 | A8 bodies 4 5 in component "Housing"
extrude "Extrusion of the housing's side mounts base support." [rolled back] taper angle 0 in component "Housing"
component "Housing" placed x (1, 0, 0) y (0, 1, 0) z (0, 0, 1) at (0, 0, 0)
component "PCBs" placed x (1, 0, 0) y (0, 1, 0) z (0, 0, 1) at (2, 0, -2.8)
component "DSensor" placed x (1, 0, 0) y (0, 1, 0) z (0, 0, 1) at (0, 0, 3.5) in component "PCBs"
component "Perf" placed x (1, 0, 0) y (0, 1, 0) z (0, 0, 1) at (0, 0, 0) in component "PCBs"
component "Wemos" placed x (1, 0, 0) y (0, 1, 0) z (0, 0, 1) at (0, 0, 3.5) in component "PCBs"
component "Headers" placed x (1, 0, 0) y (0, 1, 0) z (0, 0, 1) at (-2, 0, 2.8) in component "PCBs"
hidden bodies 4
equation "s_tolerance = 0.1 mm" comment "Small tolerance of the 3d printer."
equation "b_tolerance = 0.3 mm" comment "Bigger tolerance of the 3d printer."
equation "wemos_pcb_length = 35 mm" comment "Length of the wemos board."
equation "wemos_pcb_width = 25 mm" comment "Width of the wemos board."
equation "wemos_pcb_thickness = 1.2 mm" comment "Thickness of the wemos board."
equation "dSensor_pcb_length = 25 mm" comment "Length of the distance sensor board (VL53L0X)."
equation "dSensor_pcb_width = 17.8 mm" comment "Width of the distance sensor board (VL53L0X)."
equation "dSensor_pcb_thickness = 1.6 mm" comment "Thickness of the distance sensor board (VL53L0X)."
equation "perf_length = 50 mm" comment "Length of the perf board."
equation "perf_width = 32 mm" comment "Width of the perf board."
equation "perf_thickness = 1.2 mm" comment "Thickness of the perf board."
equation "d12 = perf_width"
equation "d13 = perf_length"
equation "d14 = perf_thickness"
equation "d16 = dSensor_pcb_length"
equation "d17 = dSensor_pcb_width"
equation "d21 = d20 * 0.85"
equation "d22 = d20 * 0.85"
equation "d24 = dSensor_pcb_thickness"
equation "d26 = wemos_pcb_length"
equation "d27 = wemos_pcb_width"
equation "d29 = d28"
equation "d31 = d30"
equation "d35 = wemos_pcb_thickness"
equation "headers_support_width = 2.5 mm" comment "The width of the plastic support for the header pins."
equation "wall_thickness = 1.5 mm" comment "Thickness of the housing walls."
equation "cavity_spacing = 2 mm" comment "Spacing/gap for the components inside the housing cavity."
equation "housing_length = perf_length + ( 2 * wall_thickness ) + ( 2 * cavity_spacing )" comment "Length of the housing/case."
equation "housing_width = wemos_pcb_length + ( 2 * cavity_spacing ) + ( 2 * wall_thickness )" comment "Width of the housing/case."
equation "housing_depth = 14 mm + cavity_spacing + ( 2 * wall_thickness )" comment "Depth of the housing/case."
equation "d43 = housing_width"
equation "d44 = housing_length"
equation "housing_mScrews_hole_diam = 3 mm" comment "Diameter of the mounting screws holes for the housing."
equation "housing_mScrews_offset = 1 mm" comment "Offset from the mounting screws holes diameter."
equation "d47 = housing_mScrews_hole_diam"
equation "d48 = housing_mScrews_offset"
equation "d49 = wall_thickness"
equation "d50 = ( housing_mScrews_hole_diam / 2 ) + housing_mScrews_offset + ( 2 * wall_thickness )"
equation "housing_rim_depth = wall_thickness + 1 mm" comment "Depth of the housing rim."
equation "d57 = -wall_thickness"
equation "d58 = -( wall_thickness - ( 2 * b_tolerance ) )"
equation "d59 = -( wall_thickness - ( 3 * b_tolerance ) )"
equation "d71 = -( housing_depth / 2 )"
equation "d72 = wall_thickness"
equation "d76 = housing_rim_depth"
equation "d78 = housing_rim_depth + ( 2 * cavity_spacing )"
equation "d79 = wall_thickness"
equation "d83 = housing_rim_depth + b_tolerance"
equation "d87 = dSensor_pcb_length / 2"
equation "d88 = dSensor_pcb_width / 2"
equation "d91 = dSensor_pcb_width / 2"
equation "d92 = d90"
equation "d93 = d89"
equation "d94 = d91"
equation "d101 = wemos_pcb_width / 2"
equation "d105 = headers_support_width"
equation "d106 = headers_support_width"
equation "d107 = headers_support_width"
equation "d110 = -wall_thickness"
equation "d112 = -( wall_thickness + perf_thickness + b_tolerance )"
equation "d113 = -wall_thickness"
equation "d121 = -( ( housing_depth / 2 ) - ( wall_thickness ) )"
equation "d122 = wall_thickness"
equation "snap_width = 3.5 mm" comment "Width of the housing's joining big snaps."
equation "bSnap_length = 8 mm" comment "Length of the housing's joining snaps."
equation "d127 = bSnap_length + b_tolerance"
equation "d128 = snap_width + b_tolerance"
equation "sSnap_length = 5 mm" comment "Length of the housing's joining small snaps."
equation "snap_thickness = 1.4 mm" comment "Thickness of the housing's joining snaps."
equation "d133 = sSnap_length + b_tolerance"
equation "d134 = snap_width"
equation "snap_insert_depth = 0.8 mm" comment "Depth of the insert for the joining snaps to rest in."
equation "d138 = -snap_insert_depth"
equation "d140 = -snap_insert_depth"
equation "d142 = -snap_insert_depth"
equation "usb_hole_width = 6 mm" comment "Width of the hole for the usb."
equation "usb_hole_length = 12 mm" comment "Length of the hole for the usb."
equation "d146 = usb_hole_length"
equation "d147 = usb_hole_width"
equation "d152 = -snap_insert_depth"
equation "snap_body_length = 12 mm" comment "Length of the snap's body from the top housing."
equation "d157 = bSnap_length"
equation "d158 = snap_body_length"
equation "d159 = d130"
equation "d160 = b_tolerance"
equation "d161 = sSnap_length"
equation "d162 = snap_body_length"
equation "d163 = d135"
equation "d164 = b_tolerance"
equation "d165 = snap_thickness"
equation "d176 = snap_thickness"
equation "d191 = housing_mScrews_hole_diam"
equation "d192 = housing_mScrews_offset"
equation "d193 = wall_thickness"
equation "d194 = ( housing_mScrews_hole_diam / 2 ) + housing_mScrews_offset + ( 2 * wall_thickness )"
equation "d197 = -wall_thickness"
equation "d199 = -wall_thickness"
equation "d200 = -wall_thickness"
equation "d202 = -( ( housing_depth / 2 ) - wall_thickness )"
named bodies: "perf board body", "dSensor board body", "wemos board body", "bottom body", "top body", "dSensor sensor body", "dSensor connector1 body", "dSensor connector2 body", "wemos wifi mod body", "header row1 body", "header row2 body", "header row3 body", "snap1", "snap2", "snap3", "snap4", "snap5"
